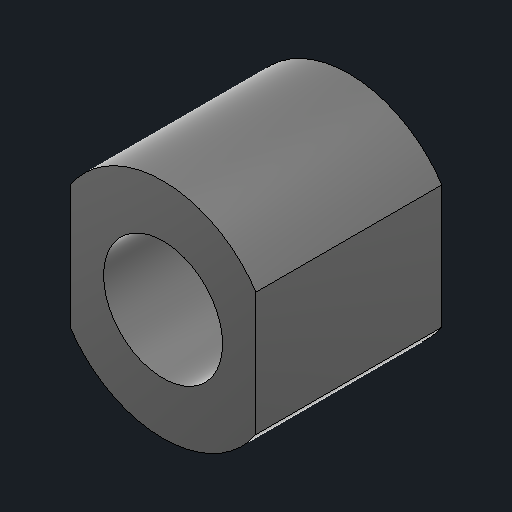
# Autodesk Inventor part: TR16-round-nut-envelope
Saved by Autodesk Inventor 2027.1 (Build 311270010, 270A)
## iProperties
Created: 2026-11-14
Part Number: TR16-round-nut-envelope
Material: Steel, Carbon
Document SubType Name: Modeling
Designer: queezz
Density: 7.85 g/cm^3
Appearance: Smooth - Black
Author: queezz
Autodesk Inventor part; units mm, degrees
ref_plane "YZ Plane" through (0, 0, 0) normal (1, 0, 0) x (0, 1, 0)
sketch "Sketch1" plane through (0, 0, 0) normal (0, 0, 1) x (1, 0, 0)
  circle A0 centre (0, 0) radius 15
  circle A1 centre (0, 0) radius 8
  constraints: 2 centre point
extrude "TR16 nut envelope 30 x 25 mm" add sketch "Sketch1" along normal blind 25
ref_plane "Work Plane1" through (-4.061, 14.5437, 12.5) normal (0.2689, -0.9632, 0) x (0, 0, 1)
sketch "Sketch2" plane through (-4.061, 14.5437, 12.5) normal (0.2689, -0.9632, 0) x (0, 0, 1)
  circle A0 centre (0, 0) radius 1.6
  constraints: 1 centre point
extrude "Dog point blind pocket" [suppressed]
ref_plane "Work Plane2" through (0, 0, 0) normal (0, 0, 1) x (1, 0, 0)
sketch "Opposed nut flats, 25 mm across" plane through (0, 0, 0) normal (0, 0, 1) x (1, 0, 0)
  line L0 (-20, -16) -> (-12.5, -16)
  line L1 (-12.5, -16) -> (-12.5, 16)
  line L2 (-12.5, 16) -> (-20, 16)
  line L3 (-20, 16) -> (-20, -16)
  line L4 (12.5, -16) -> (20, -16)
  line L5 (20, -16) -> (20, 16)
  line L6 (20, 16) -> (12.5, 16)
  line L7 (12.5, 16) -> (12.5, -16)
  constraints: 16 end point, 4 parallel, 2 horizontal, 2 perpendicular
extrude "Mill opposed flats to 25 mm across" cut sketch "Opposed nut flats, 25 mm across" along normal blind 25
body "Solid1"
